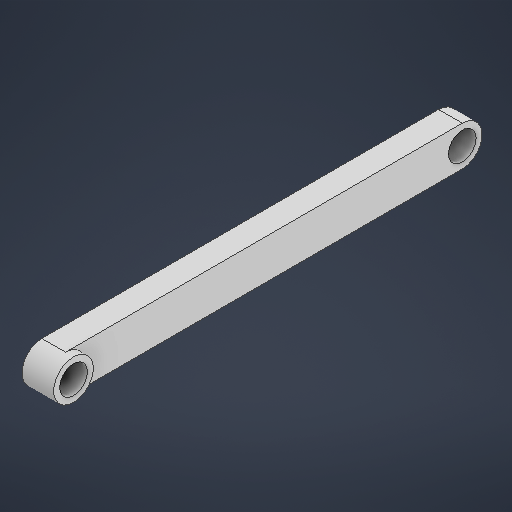
# Autodesk Inventor part: 22.10.2025-22
Saved by Autodesk Inventor 2026.1 (Build 301233020, 233B)
## iProperties
Created: 2026-01-26
Part Number: 22.10.2025-22
Material: Ogólny
Document SubType Name: Modeling
Designer: Nitro
Density: 1 g/cm^3
Appearance: Domyślna
Description: Stabilizator chwytaka
Author: Nitro
Autodesk Inventor part; units mm, degrees
ref_plane "YZ Plane" through (0, 0, 0) normal (1, 0, 0) x (0, 1, 0)
ref_plane "XZ Plane" through (0, 0, 0) normal (0, 1, 0) x (-1, 0, 0)
ref_plane "XY Plane" through (0, 0, 0) normal (0, 0, 1) x (1, 0, 0)
sketch "Szkic1" plane through (0, 0, 0) normal (1, 0, 0) x (0, 1, 0)
  line L0 (0, -25) -> (0, 25) construction
  line L1 (2.5, -25) -> (2.5, 25)
  line L2 (-2.5, 25) -> (-2.5, -25)
  arc A0 (-2.5, -25) -> (2.5, -25) centre (0, -25) ccw
  arc A1 (2.5, 25) -> (-2.5, 25) centre (0, 25) ccw
  point P0 (0, 0)
  dimension "d0" = 25
  dimension "d1" = 5
  constraints: 8 end point, 4 point on circle, 4 tangent, 2 centre point, 1 midpoint, 1 parallel, 1 vertical
  measures "d0" distance of point (0, 0) L0.end
  measures "d1" diameter of A1
extrude "Wyciągnięcie proste1" add sketch "Szkic1" along normal blind 3
sketch "Szkic2" plane through (3, 0, 0) normal (1, 0, 0) x (0, 0, -1)
  arc A0 (-25, 2.5) -> (-25, -2.5) centre (-25, 0) ccw projected
  line L0 (-25, -2.5) -> (25, -2.5) projected
  arc A1 (25, -2.5) -> (25, 2.5) centre (25, 0) ccw projected
  line L1 (25, 2.5) -> (-25, 2.5) projected
  circle A2 centre (-25, 0) radius 2.5
  point P0 (0, 0)
  constraints: 1 centre point, 1 coincident
extrude "Wyciągnięcie proste2" add sketch "Szkic2" along normal blind 1 contours A2 A0
sketch "Szkic3" plane through (4, 0, 25) normal (1, 0, 0) x (0, 0, -1)
  circle A0 centre (0, 0) radius 2.5 projected
  arc A1 (0, -2.5) -> (0, 2.5) centre (0, 0) ccw projected
  line L0 (0, -2.5) -> (50, -2.5) projected
  arc A2 (50, -2.5) -> (50, 2.5) centre (50, 0) ccw projected
  line L1 (50, 2.5) -> (0, 2.5) projected
  circle A3 centre (0, 0) radius 1.75
  circle A4 centre (50, 0) radius 1.75
  point P0 (25, 0)
  dimension "d6" = 3.5
  dimension "d7" = 3.5
  constraints: 2 centre point, 2 coincident
  measures "d6" diameter of A3
  measures "d7" diameter of A4
extrude "Wyciągnięcie proste3" cut sketch "Szkic3" against normal blind 10 contours A3 | A4
